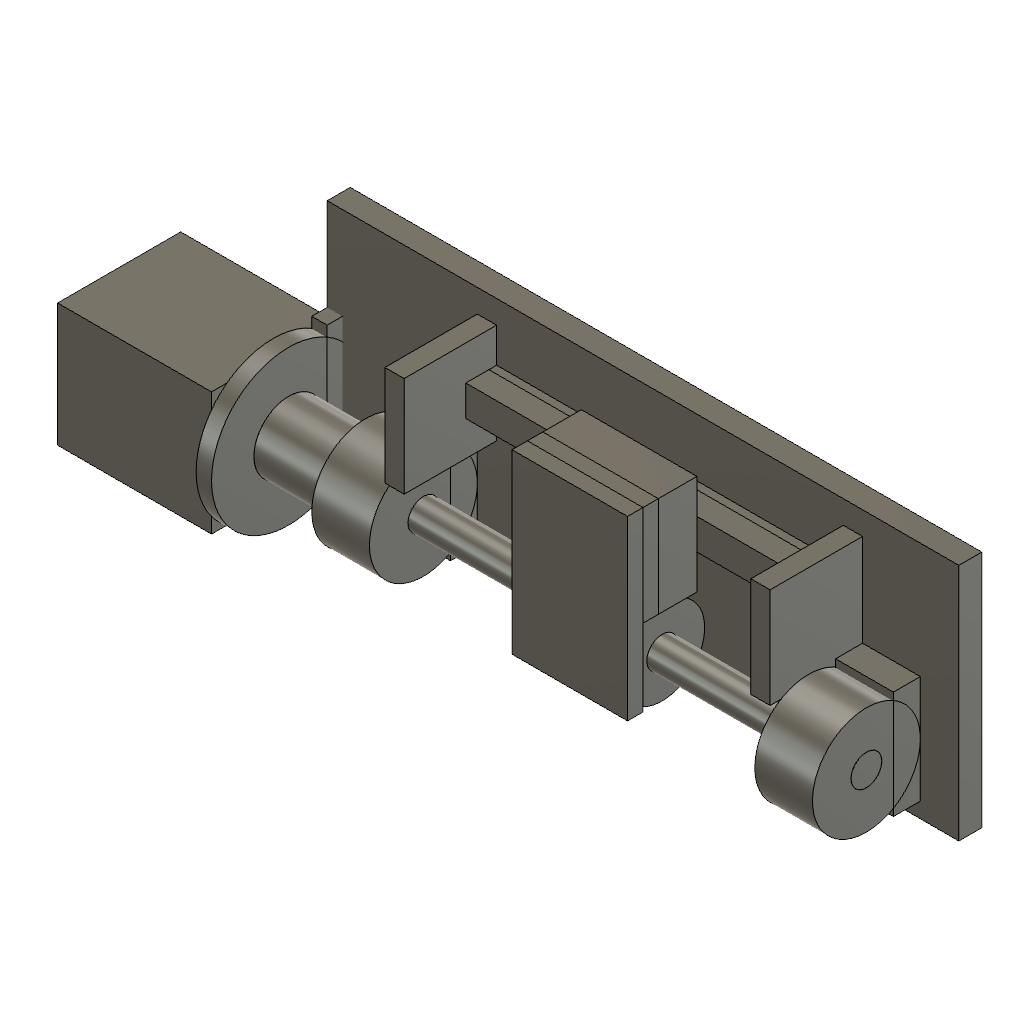
screw-stage-envelopes (Autodesk Fusion 360 design; units mm, degrees)
part number: 2026-11-06-12-59-00-464
part number: 2026-11-06-12-59-00-684
part number: 2026-11-06-12-59-00-699
part number: 2026-11-06-12-59-00-709
part number: 2026-11-06-12-59-00-725
part number: 2026-11-06-12-59-00-743
part number: 2026-11-06-12-59-00-761
part number: 2026-11-06-12-59-00-781
part number: 2026-11-06-12-59-00-803
part number: 2026-11-06-12-59-00-821
part number: 2026-11-06-12-59-00-847
part number: 2026-11-06-12-59-00-867
part number: 2026-11-06-12-59-00-888
part number: 2026-11-06-12-59-00-909
part number: 2026-11-06-12-59-00-932
part number: 2026-11-06-12-59-00-955
part number: 2026-11-06-12-59-00-979
part number: 2026-11-06-12-59-01-005
part number: 2026-11-06-12-59-01-031
part number: 2026-11-06-12-59-01-068
part number: 2026-11-06-12-59-01-097
part number: 2026-11-06-12-59-01-139
part number: 2026-11-06-12-59-01-171
Autodesk Fusion 360 part; units mm, degrees
sketch "Base envelope footprint" plane through (0, 0, 0) normal (0, 0, 1) x (1, 0, 0) in component "Base envelope"
  line L0 (0, 0) -> (164, 0)
  line L1 (164, 0) -> (164, 62)
  line L2 (164, 62) -> (0, 62)
  line L3 (0, 62) -> (0, 0)
extrude "Base envelope thickness" add sketch "Base envelope footprint" along normal blind 6 makes body 1 in component "Base envelope"
sketch "8 mm screw envelope NO THREAD section" plane through (0, 0, 0) normal (0, 0, 1) x (1, 0, 0) in component "8 mm screw envelope NO THREAD"
  circle A0 centre (0, 0) radius 4
  dimension "d19" = 8
  constraint coincident A0.centre origin
  measures "d19" diameter of A0
extrude "8 mm screw envelope NO THREAD length" add sketch "8 mm screw envelope NO THREAD section" along normal blind 140 separate body makes body 2 in component "8 mm screw envelope NO THREAD"
sketch "Nut envelope NO THREAD section" plane through (0, 0, 0) normal (0, 0, 1) x (1, 0, 0) in component "Nut envelope NO THREAD"
  circle A0 centre (0, 0) radius 8
  circle A1 centre (0, 0) radius 4
  dimension "d22" = 16
  dimension "d23" = 8
  constraint coincident A0.centre A1.centre
  measures "d22" diameter of A0
  measures "d23" diameter of A1
extrude "Nut envelope NO THREAD length" add sketch "Nut envelope NO THREAD section" along normal blind 20 separate body makes body 3 in component "Nut envelope NO THREAD"
sketch "Nut carrier sleeve envelope section" plane through (0, 0, 0) normal (0, 0, 1) x (1, 0, 0) in component "Nut carrier sleeve envelope"
  circle A0 centre (0, 0) radius 11
  circle A1 centre (0, 0) radius 8
  dimension "d26" = 22
  dimension "d27" = 16
  constraint coincident A0.centre A1.centre
  measures "d26" diameter of A0
  measures "d27" diameter of A1
extrude "Nut carrier sleeve envelope length" add sketch "Nut carrier sleeve envelope section" along normal blind 20 separate body makes body 4 in component "Nut carrier sleeve envelope"
sketch "Nut carrier left shoulder envelope section" plane through (0, 0, 0) normal (0, 0, 1) x (1, 0, 0) in component "Nut carrier left shoulder envelope"
  circle A0 centre (0, 0) radius 11
  circle A1 centre (0, 0) radius 4
  dimension "d30" = 22
  dimension "d31" = 8
  constraint coincident A0.centre A1.centre
  measures "d30" diameter of A0
  measures "d31" diameter of A1
extrude "Nut carrier left shoulder envelope length" add sketch "Nut carrier left shoulder envelope section" along normal blind 2 separate body makes body 5 in component "Nut carrier left shoulder envelope"
sketch "Nut carrier right removable cap envelope section" plane through (0, 0, 0) normal (0, 0, 1) x (1, 0, 0) in component "Nut carrier right removable cap envelope"
  circle A0 centre (0, 0) radius 11
  circle A1 centre (0, 0) radius 4
  dimension "d34" = 22
  dimension "d35" = 8
  constraint coincident A0.centre A1.centre
  measures "d34" diameter of A0
  measures "d35" diameter of A1
extrude "Nut carrier right removable cap envelope length" add sketch "Nut carrier right removable cap envelope section" along normal blind 2 separate body makes body 6 in component "Nut carrier right removable cap envelope"
sketch "Fixed axial support selection required section" plane through (0, 0, 0) normal (0, 0, 1) x (1, 0, 0) in component "Fixed axial support selection required"
  circle A0 centre (0, 0) radius 14
  circle A1 centre (0, 0) radius 4
  dimension "d38" = 28
  dimension "d39" = 8
  constraint coincident A0.centre A1.centre
  measures "d38" diameter of A0
  measures "d39" diameter of A1
extrude "Fixed axial support selection required length" add sketch "Fixed axial support selection required section" along normal blind 15 separate body makes body 7 in component "Fixed axial support selection required"
sketch "Fixed axial support selection required foot footprint" plane through (0, 0, 0) normal (0, 0, 1) x (1, 0, 0) in component "Fixed axial support selection required foot"
  line L0 (0, 0) -> (15, 0)
  line L1 (15, 0) -> (15, 28)
  line L2 (15, 28) -> (0, 28)
  line L3 (0, 28) -> (0, 0)
extrude "Fixed axial support selection required foot thickness" add sketch "Fixed axial support selection required foot footprint" along normal blind 7 separate body makes body 8 in component "Fixed axial support selection required foot"
sketch "Floating radial support selection required section" plane through (0, 0, 0) normal (0, 0, 1) x (1, 0, 0) in component "Floating radial support selection required"
  circle A0 centre (0, 0) radius 14
  circle A1 centre (0, 0) radius 4
  dimension "d44" = 28
  dimension "d45" = 8
  constraint coincident A0.centre A1.centre
  measures "d44" diameter of A0
  measures "d45" diameter of A1
extrude "Floating radial support selection required length" add sketch "Floating radial support selection required section" along normal blind 15 separate body makes body 9 in component "Floating radial support selection required"
sketch "Floating radial support selection required foot footprint" plane through (0, 0, 0) normal (0, 0, 1) x (1, 0, 0) in component "Floating radial support selection required foot"
  line L0 (0, 0) -> (15, 0)
  line L1 (15, 0) -> (15, 28)
  line L2 (15, 28) -> (0, 28)
  line L3 (0, 28) -> (0, 0)
extrude "Floating radial support selection required foot thickness" add sketch "Floating radial support selection required foot footprint" along normal blind 7 separate body makes body 10 in component "Floating radial support selection required foot"
sketch "Guide rail envelope footprint" plane through (0, 0, 0) normal (0, 0, 1) x (1, 0, 0) in component "Guide rail envelope"
  line L0 (0, 0) -> (90, 0)
  line L1 (90, 0) -> (90, 8)
  line L2 (90, 8) -> (0, 8)
  line L3 (0, 8) -> (0, 0)
extrude "Guide rail envelope thickness" add sketch "Guide rail envelope footprint" along normal blind 6 separate body makes body 11 in component "Guide rail envelope"
sketch "Guide mounting pedestal envelope footprint" plane through (0, 0, 0) normal (0, 0, 1) x (1, 0, 0) in component "Guide mounting pedestal envelope"
  line L0 (0, 0) -> (90, 0)
  line L1 (90, 0) -> (90, 8)
  line L2 (90, 8) -> (0, 8)
  line L3 (0, 8) -> (0, 0)
extrude "Guide mounting pedestal envelope thickness" add sketch "Guide mounting pedestal envelope footprint" along normal blind 2 separate body makes body 12 in component "Guide mounting pedestal envelope"
sketch "Guide block mid travel envelope footprint" plane through (0, 0, 0) normal (0, 0, 1) x (1, 0, 0) in component "Guide block mid travel envelope"
  line L0 (0, 0) -> (30, 0)
  line L1 (30, 0) -> (30, 26)
  line L2 (30, 26) -> (0, 26)
  line L3 (0, 26) -> (0, 0)
extrude "Guide block mid travel envelope thickness" add sketch "Guide block mid travel envelope footprint" along normal blind 10 separate body makes body 13 in component "Guide block mid travel envelope"
sketch "Carriage bridge envelope footprint" plane through (0, 0, 0) normal (0, 0, 1) x (1, 0, 0) in component "Carriage bridge envelope"
  line L0 (0, 0) -> (30, 0)
  line L1 (30, 0) -> (30, 46)
  line L2 (30, 46) -> (0, 46)
  line L3 (0, 46) -> (0, 0)
extrude "Carriage bridge envelope thickness" add sketch "Carriage bridge envelope footprint" along normal blind 4 separate body makes body 14 in component "Carriage bridge envelope"
sketch "Block standoff envelope footprint" plane through (0, 0, 0) normal (0, 0, 1) x (1, 0, 0) in component "Block standoff envelope"
  line L0 (0, 0) -> (30, 0)
  line L1 (30, 0) -> (30, 26)
  line L2 (30, 26) -> (0, 26)
  line L3 (0, 26) -> (0, 0)
extrude "Block standoff envelope thickness" add sketch "Block standoff envelope footprint" along normal blind 4 separate body makes body 15 in component "Block standoff envelope"
sketch "Removable end stop envelope 15 footprint" plane through (0, 0, 0) normal (0, 0, 1) x (1, 0, 0) in component "Removable end stop envelope 15"
  line L0 (0, 0) -> (5, 0)
  line L1 (5, 0) -> (5, 26)
  line L2 (5, 26) -> (0, 26)
  line L3 (0, 26) -> (0, 0)
extrude "Removable end stop envelope 15 thickness" add sketch "Removable end stop envelope 15 footprint" along normal blind 24 separate body makes body 16 in component "Removable end stop envelope 15"
sketch "Removable end stop envelope 110 footprint" plane through (0, 0, 0) normal (0, 0, 1) x (1, 0, 0) in component "Removable end stop envelope 110"
  line L0 (0, 0) -> (5, 0)
  line L1 (5, 0) -> (5, 26)
  line L2 (5, 26) -> (0, 26)
  line L3 (0, 26) -> (0, 0)
extrude "Removable end stop envelope 110 thickness" add sketch "Removable end stop envelope 110 footprint" along normal blind 24 separate body makes body 17 in component "Removable end stop envelope 110"
sketch "Flexible coupling envelope NOT thrust support section" plane through (0, 0, 0) normal (0, 0, 1) x (1, 0, 0) in component "Flexible coupling envelope NOT thrust support"
  circle A0 centre (0, 0) radius 9
  circle A1 centre (0, 0) radius 4
  dimension "d64" = 18
  dimension "d65" = 8
  constraint coincident A0.centre A1.centre
  measures "d64" diameter of A0
  measures "d65" diameter of A1
extrude "Flexible coupling envelope NOT thrust support length" add sketch "Flexible coupling envelope NOT thrust support section" along normal blind 20 separate body makes body 18 in component "Flexible coupling envelope NOT thrust support"
sketch "Motor generic 32 square envelope footprint" plane through (0, 0, 0) normal (0, 0, 1) x (1, 0, 0) in component "Motor generic 32 square envelope"
  line L0 (0, 0) -> (40, 0)
  line L1 (40, 0) -> (40, 32)
  line L2 (40, 32) -> (0, 32)
  line L3 (0, 32) -> (0, 0)
extrude "Motor generic 32 square envelope thickness" add sketch "Motor generic 32 square envelope footprint" along normal blind 32 separate body makes body 19 in component "Motor generic 32 square envelope"
sketch "Motor mounting plate clearance envelope section" plane through (0, 0, 0) normal (0, 0, 1) x (1, 0, 0) in component "Motor mounting plate clearance envelope"
  circle A0 centre (0, 0) radius 20
  circle A1 centre (0, 0) radius 9
  dimension "d70" = 40
  dimension "d71" = 18
  constraint coincident A0.centre A1.centre
  measures "d70" diameter of A0
  measures "d71" diameter of A1
extrude "Motor mounting plate clearance envelope length" add sketch "Motor mounting plate clearance envelope section" along normal blind 4 separate body makes body 20 in component "Motor mounting plate clearance envelope"
sketch "Motor bracket foot envelope footprint" plane through (0, 0, 0) normal (0, 0, 1) x (1, 0, 0) in component "Motor bracket foot envelope"
  line L0 (0, 0) -> (4, 0)
  line L1 (4, 0) -> (4, 40)
  line L2 (4, 40) -> (0, 40)
  line L3 (0, 40) -> (0, 0)
extrude "Motor bracket foot envelope thickness" add sketch "Motor bracket foot envelope footprint" along normal blind 10 separate body makes body 21 in component "Motor bracket foot envelope"
sketch "Motor shaft generic envelope section" plane through (0, 0, 0) normal (0, 0, 1) x (1, 0, 0) in component "Motor shaft generic envelope"
  circle A0 centre (0, 0) radius 2.5
  dimension "d76" = 5
  constraint coincident A0.centre origin
  measures "d76" diameter of A0
extrude "Motor shaft generic envelope length" add sketch "Motor shaft generic envelope section" along normal blind 13 separate body makes body 22 in component "Motor shaft generic envelope"
component "Base envelope" placed x (1, 0, 0) y (0, 1, 0) z (0, 0, 1) at (-24, -18, 0)
component "8 mm screw envelope NO THREAD" placed x (0, 0, -1) y (0, 1, 0) z (1, 0, 0) at (-10, 0, 20)
component "Nut envelope NO THREAD" placed x (0, 0, -1) y (0, 1, 0) z (1, 0, 0) at (55, 0, 20)
component "Nut carrier sleeve envelope" placed x (0, 0, -1) y (0, 1, 0) z (1, 0, 0) at (55, 0, 20)
component "Nut carrier left shoulder envelope" placed x (0, 0, -1) y (0, 1, 0) z (1, 0, 0) at (53, 0, 20)
component "Nut carrier right removable cap envelope" placed x (0, 0, -1) y (0, 1, 0) z (1, 0, 0) at (75, 0, 20)
component "Fixed axial support selection required" placed x (0, 0, -1) y (0, 1, 0) z (1, 0, 0) at (0, 0, 20)
component "Fixed axial support selection required foot" placed x (1, 0, 0) y (0, 1, 0) z (0, 0, 1) at (0, -14, 6)
component "Floating radial support selection required" placed x (0, 0, -1) y (0, 1, 0) z (1, 0, 0) at (115, 0, 20)
component "Floating radial support selection required foot" placed x (1, 0, 0) y (0, 1, 0) z (0, 0, 1) at (115, -14, 6)
component "Guide rail envelope" placed x (1, 0, 0) y (0, 1, 0) z (0, 0, 1) at (20, 21, 8)
component "Guide mounting pedestal envelope" placed x (1, 0, 0) y (0, 1, 0) z (0, 0, 1) at (20, 21, 6)
component "Guide block mid travel envelope" placed x (1, 0, 0) y (0, 1, 0) z (0, 0, 1) at (50, 12, 14)
component "Carriage bridge envelope" placed x (1, 0, 0) y (0, 1, 0) z (0, 0, 1) at (50, -8, 28)
component "Block standoff envelope" placed x (1, 0, 0) y (0, 1, 0) z (0, 0, 1) at (50, 12, 24)
component "Removable end stop envelope 15" placed x (1, 0, 0) y (0, 1, 0) z (0, 0, 1) at (15, 12, 6)
component "Removable end stop envelope 110" placed x (1, 0, 0) y (0, 1, 0) z (0, 0, 1) at (110, 12, 6)
component "Flexible coupling envelope NOT thrust support" placed x (0, 0, -1) y (0, 1, 0) z (1, 0, 0) at (-20, 0, 20)
component "Motor generic 32 square envelope" placed x (1, 0, 0) y (0, 1, 0) z (0, 0, 1) at (-64, -16, 4)
component "Motor mounting plate clearance envelope" placed x (0, 0, -1) y (0, 1, 0) z (1, 0, 0) at (-24, 0, 20)
component "Motor bracket foot envelope" placed x (1, 0, 0) y (0, 1, 0) z (0, 0, 1) at (-24, -20, 0)
component "Motor shaft generic envelope" placed x (0, 0, -1) y (0, 1, 0) z (1, 0, 0) at (-24, 0, 20)
equation "travel = 50 mm" comment "Study reference input; envelope positions require manual regeneration"
equation "lead = 2 mm" comment "Study reference input; envelope positions require manual regeneration"
equation "screw_diameter = 8 mm" comment "Study reference input; envelope positions require manual regeneration"
equation "screw_overall = 140 mm" comment "Study reference input; envelope positions require manual regeneration"
equation "nut_length = 20 mm" comment "Study reference input; envelope positions require manual regeneration"
equation "carriage_length = 30 mm" comment "Study reference input; envelope positions require manual regeneration"
equation "travel_start_x = 40 mm" comment "Study reference input; envelope positions require manual regeneration"
equation "travel_end_x = 90 mm" comment "Study reference input; envelope positions require manual regeneration"
equation "thread_start_x = 25 mm" comment "Study reference input; envelope positions require manual regeneration"
equation "thread_end_x = 105 mm" comment "Study reference input; envelope positions require manual regeneration"
equation "guide_offset = 25 mm" comment "Study reference input; envelope positions require manual regeneration"
equation "guide_start_x = 20 mm" comment "Study reference input; envelope positions require manual regeneration"
equation "guide_end_x = 110 mm" comment "Study reference input; envelope positions require manual regeneration"
equation "screw_axis_height = 20 mm" comment "Study reference input; envelope positions require manual regeneration"
equation "mechanical_stop_low_x = 20 mm" comment "Study reference input; envelope positions require manual regeneration"
equation "mechanical_stop_high_x = 110 mm" comment "Study reference input; envelope positions require manual regeneration"
named bodies: "Base envelope", "8 mm screw envelope NO THREAD", "Nut envelope NO THREAD", "Nut carrier sleeve envelope", "Nut carrier left shoulder envelope", "Nut carrier right removable cap envelope", "Fixed axial support selection required", "Fixed axial support selection required foot", "Floating radial support selection required", "Floating radial support selection required foot", "Guide rail envelope", "Guide mounting pedestal envelope", "Guide block mid travel envelope", "Carriage bridge envelope", "Block standoff envelope", "Removable end stop envelope 15", "Removable end stop envelope 110", "Flexible coupling envelope NOT thrust support", "Motor generic 32 square envelope", "Motor mounting plate clearance envelope", "Motor bracket foot envelope", "Motor shaft generic envelope"
